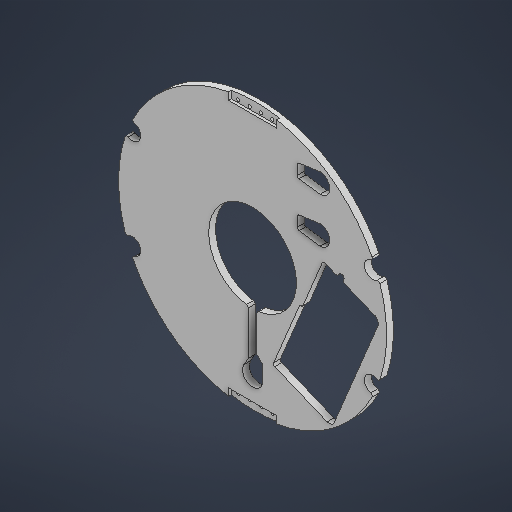
# Autodesk Inventor part: macro_mfd1004
Saved by Autodesk Inventor 2026.4 (Build 304435000, 435)
## iProperties
Created: 2026-11-03
Part Number: macro_mfd1004
Material: Genérico
Document SubType Name: Modeling
Designer: User
Density: 1 g/cm^3
Appearance: Padrão
Author: User
Autodesk Inventor part; units mm, degrees
ref_plane "YZ Plane" through (0, 0, 0) normal (1, 0, 0) x (0, 1, 0)
ref_plane "XZ Plane" through (0, 0, 0) normal (0, 1, 0) x (-1, 0, 0)
sketch "Sketch_Base_Disk" plane through (0, 0, 0) normal (0, 0, 1) x (1, 0, 0)
  circle A0 centre (0, 0) radius 195.5038
  dimension "d42" = 391.0076
  constraints: 1 centre point
  measures "d42" diameter of A0
extrude "Base_Disk" add sketch "Sketch_Base_Disk" along normal blind 10.0076
ref_plane "Datum_A_Front_Face" through (0, 0, 10.0076) normal (0, 0, 1) x (1, 0, 0)
sketch "Sketch_Central_Bore_Keyhole" plane through (0, 0, 0) normal (0, 0, 1) x (1, 0, 0)
  circle A0 centre (0.0002, 0.1535) radius 64.008
  line L0 (-6.2988, -51.2066) -> (6.4012, -51.2066)
  line L1 (6.4012, -51.2066) -> (6.4012, -130.0469)
  line L2 (6.4012, -130.0469) -> (-6.2988, -130.0469)
  line L3 (-6.2988, -130.0469) -> (-6.2988, -51.2066)
  circle A1 centre (0.051, -148.5127) radius 14.732
  line L4 (0.0002, 243.0256) -> (0.0002, -242.7185)
  line L5 (14.7822, -148.6669) -> (14.7822, -127.3309)
  line L6 (14.7822, -127.3309) -> (89.3002, -201.8489)
  line L7 (14.7822, -127.3309) -> (6.4012, -118.9484)
  line L8 (-6.2988, -130.0469) -> (-67.6388, -236.2908)
  line L9 (-6.2988, -130.0469) -> (-12.7075, -141.1471)
  point P0 (6.4012, -63.5336)
  point P1 (-6.2988, -63.5438)
  point P2 (-12.7073, -141.1467)
  point P3 (14.7822, -148.3584)
  dimension "d31" = 29.464
  dimension "d28" = 128.016
  dimension "d29" = 12.7
  dimension "d30" = 148.6662
  dimension "d33" = 21.336
  dimension "d34" = 45
  dimension "d35" = 18.4658
  dimension "d36" = 30
  constraints: 20 end point, 2 parallel, 2 point on line, 2 vertical, 1 centre point, 1 horizontal, 1 midpoint, 1 perpendicular, 4 other
  measures "d28" diameter of A0
  measures "d29" distance between parallel lines of L3 L1
  measures "d30" distance of point (0.051, -148.513) A0.centre
  measures "d33" distance of L5.start L5.end
  measures "d34" angle of L4 L6
  measures "d35" distance from line of L2 point (0.051, -148.513)
  measures "d36" angle of L4 L8
extrude "Central_Bore_Keyhole" cut sketch "Sketch_Central_Bore_Keyhole" along normal through all both and the other way through all
sketch "Sketch_Flats_Notches" plane through (0, 0, 0) normal (0, 0, 1) x (1, 0, 0)
  line L0 (0, 195.5038) -> (0, -195.5038)
  line L1 (195.5038, 0) -> (-195.5038, 0)
  line L2 (-270.4451, 112.022) -> (270.4451, -112.022)
  line L3 (297.3467, 123.165) -> (-297.3467, -123.165)
  circle A0 centre (0, 0) radius 195.5038 projected
  line L4 (180.622, -74.8161) -> (174.99, -72.4832)
  circle A1 centre (174.99, -72.4832) radius 12.0015
  circle A2 centre (0, 0) radius 189.4078
  circle A3 centre (-174.99, -72.4832) radius 12.0015
  circle A4 centre (-174.99, 72.4832) radius 12.0015
  circle A5 centre (174.99, 72.4832) radius 12.0015
  dimension "d21" = 67.5
  dimension "d22" = 67.5
  dimension "d23" = 6.096
  dimension "d24" = 24.003
  dimension "d25" = 24.003
  dimension "d26" = 24.003
  dimension "d27" = 24.003
  constraints: 10 end point, 5 centre point, 5 point on circle, 5 point on line, 4 midpoint, 2 coincident, 1 vertical
  measures "d21" angle of L0 L2
  measures "d22" angle of L0 L3
  measures "d23" distance of L4.start L4.end
  measures "d24" diameter of A1
  measures "d25" diameter of A3
  measures "d26" diameter of A4
  measures "d27" diameter of A5
extrude "Flats_Notches_DetailA" cut sketch "Sketch_Flats_Notches" along normal through all both and the other way through all contours A5 L3 A0 | A0 L3 A2 A5 | A4 A2 L2 A0 | A0 L2 A4 | A2 L3 A5 | A4 L2 A2 | A0 A5 A2 L3 | L3 A5 A0 | A0 A4 L2 | L2 A2 A4 A0 | A4 A2 L2 | A1 A2 L2 | L2 A2 A1 | L3 A2 A5 | A3 A2 L3 | L3 A2 A3 | A3 A0 L3 A2 | A2 L2 A0 A1 | A1 A0 L2 A2 | A2 L3 A0 A3 | A3 L3 A0 | A0 L2 A1 | A1 L2 A0 | A0 L3 A3
sketch "Sketch_Mount_Pockets" plane through (0, 0, 10.0076) normal (0, 0, 1) x (1, 0, 0)
  line L0 (-35.1155, 181.61) -> (35.1155, 181.61)
  line L1 (35.1155, 181.61) -> (35.1155, 215.9)
  line L2 (35.1155, 215.9) -> (-35.1155, 215.9)
  line L3 (-35.1155, 215.9) -> (-35.1155, 181.61)
  line L4 (-35.1155, -215.9) -> (35.1155, -215.9)
  line L5 (35.1155, -215.9) -> (35.1155, -181.61)
  line L6 (35.1155, -181.61) -> (-35.1155, -181.61)
  line L7 (-35.1155, -181.61) -> (-35.1155, -215.9)
  constraints: 16 end point, 4 parallel, 2 horizontal, 2 perpendicular
extrude "Front_Mount_Pockets" cut sketch "Sketch_Mount_Pockets" against normal blind 3.9624
sketch "Sketch_Back_Pockets" plane through (0, 0, 0) normal (0, 0, 1) x (1, 0, 0)
  line L0 (0, 0) -> (98.425, 0)
  line L1 (98.425, 0) -> (98.425, 287.782)
  arc A0 (6.4012, -63.5336) -> (-6.2988, -63.5438) centre (0.0002, 0.1535) ccw projected
  circle A1 centre (0.0002, 0.1535) radius 64.008
  line L2 (0.0002, 195.8109) -> (0.0002, -195.5038)
  arc A2 (-176.3434, -84.4082) -> (176.3434, -84.4082) centre (0, 0) ccw projected
  line L3 (-195.5038, 0) -> (195.5038, 0)
  arc A3 (98.425, 64.135) -> (98.425, 92.583) centre (98.425, 78.359) ccw
  line L4 (98.425, 78.359) -> (65.151, 78.359)
  line L5 (65.151, 85.2362) -> (65.151, 71.4818)
  line L6 (98.425, 92.583) -> (67.7728, 88.2542)
  line L7 (67.7728, 68.4637) -> (98.425, 64.135)
  arc A4 (67.7728, 88.2542) -> (65.151, 85.2362) centre (68.199, 85.2362) ccw
  arc A5 (65.151, 71.4818) -> (67.7728, 68.4637) centre (68.199, 71.4818) ccw
  arc A6 (98.425, 129.667) -> (98.425, 158.115) centre (98.425, 143.891) ccw
  line L8 (98.425, 143.891) -> (65.151, 143.891)
  line L9 (65.151, 150.7682) -> (65.151, 137.0138)
  line L10 (98.425, 158.115) -> (67.7728, 153.7862)
  line L11 (98.425, 129.667) -> (67.7728, 133.9957)
  arc A7 (67.7728, 153.7862) -> (65.151, 150.7682) centre (68.199, 150.7682) ccw
  arc A8 (65.151, 137.0138) -> (67.7728, 133.9957) centre (68.199, 137.0138) ccw
  line L12 (98.425, 129.667) -> (65.151, 129.667)
  line L13 (98.425, 92.583) -> (65.151, 92.583)
  point P0 (65.151, 68.834)
  point P1 (65.151, 87.884)
  point P2 (65.151, 134.366)
  point P3 (65.151, 153.416)
  dimension "d57" = 98.425
  dimension "d90" = 90
  dimension "d94" = 14.224
  dimension "d95" = 78.359
  dimension "d96" = 33.274
  dimension "d97" = 19.05
  dimension "d98" = 3.048
  dimension "d99" = 14.224
  dimension "d100" = 143.891
  dimension "d101" = 33.274
  dimension "d102" = 19.05
  dimension "d103" = 3.048
  dimension "d104" = 8.038
  dimension "d105" = 8.038
  constraints: 26 end point, 13 point on circle, 9 point on line, 8 tangent, 7 centre point, 5 horizontal, 4 midpoint, 3 vertical, 2 coincident, 2 equal radius, 10 other
  measures "d57" distance of L0.start L0.end
  measures "d90" angle to the sketch y axis of L0
  measures "d94" radius of A3
  measures "d95" distance of L4.start L0.end
  measures "d96" distance of L4.start L4.end
  measures "d97" distance of point (65.151, 87.884) point (65.151, 68.834)
  measures "d98" radius of A4
  measures "d99" radius of A6
  measures "d100" distance of L0.end L8.start
  measures "d101" distance of L8.start L8.end
  measures "d102" distance of point (65.151, 153.416) point (65.151, 134.366)
  measures "d103" radius of A7
  measures "d104" angle of L13 L6
  measures "d105" angle of L11 L12
extrude "Back_Pockets_and_Slots" cut sketch "Sketch_Back_Pockets" along normal through all contours L11 A8 L9 L8 L1 | L1 A6 | L7 A5 L5 L4 L1 | L1 A3 | L4 L5 A4 L6 L1 | L8 L9 A7 L10 L1
sketch "Sketch_Mount_Holes" plane through (0, 0, 10.0076) normal (0, 0, 1) x (1, 0, 0)
  circle A0 centre (-24.8158, 185.42) radius 2.4892
  circle A1 centre (-24.8158, -185.42) radius 2.4892
  circle A2 centre (-8.255, 185.42) radius 2.4892
  circle A3 centre (-8.255, -185.42) radius 2.4892
  circle A4 centre (8.255, 185.42) radius 2.4892
  circle A5 centre (8.255, -185.42) radius 2.4892
  circle A6 centre (24.8158, 185.42) radius 2.4892
  circle A7 centre (24.8158, -185.42) radius 2.4892
  constraints: 8 centre point
extrude "Mount_Pocket_Holes" cut sketch "Sketch_Mount_Holes" along normal through all both and the other way through all
sketch "Esboço11" plane through (0, 0, 0) normal (0, 0, -1) x (-1, 0, 0)
  arc A0 (-176.3434, -84.4082) -> (-184.3792, -65.008) centre (-174.99, -72.4832) ccw projected
  circle A1 centre (-174.99, -72.4832) radius 12.0015
  line L0 (174.99, 72.4832) -> (-174.99, -72.4832)
  line L1 (0, 0) -> (-67.6071, -28.0038)
  line L2 (-67.6071, -28.0038) -> (-30.7085, -117.085)
  line L3 (-32.358, -121.0674) -> (-108.7651, -152.7162)
  line L4 (-119.053, -148.4549) -> (-182.9727, 5.8611)
  line L5 (-67.6071, -28.0038) -> (-67.9941, -27.0694)
  line L6 (-70.8101, -25.1878) -> (-70.6684, -25.1878)
  line L7 (-73.4844, -23.3062) -> (-101.6776, 44.7583)
  arc A2 (-178.7113, 16.149) -> (-182.9727, 5.8611) centre (-175.6981, 8.8744) ccw
  arc A3 (-119.053, -148.4549) -> (-108.7651, -152.7162) centre (-111.7783, -145.4416) ccw
  arc A4 (-101.6776, 44.7583) -> (-105.66, 46.4078) centre (-104.4936, 43.5919) ccw
  arc A5 (-67.9941, -27.0694) -> (-70.8101, -25.1878) centre (-70.8101, -28.2358) ccw
  arc A6 (-73.4844, -23.3062) -> (-70.6684, -25.1878) centre (-70.6684, -22.1398) ccw
  arc A7 (-32.358, -121.0674) -> (-30.7085, -117.085) centre (-33.5244, -118.2514) ccw
  line L8 (-132.8273, 38.4539) -> (-133.4106, 39.8619)
  line L9 (-125.4354, 41.5157) -> (-126.0186, 42.9237)
  line L10 (-130.001, 44.5733) -> (-131.761, 43.8443)
  line L11 (-134.4769, 34.4715) -> (-178.7113, 16.149)
  line L12 (-121.453, 39.8662) -> (-105.66, 46.4078)
  arc A8 (-125.4354, 41.5157) -> (-121.453, 39.8662) centre (-122.6194, 42.6822) ccw
  arc A9 (-131.761, 43.8443) -> (-133.4106, 39.8619) centre (-130.5946, 41.0283) ccw
  arc A10 (-134.4769, 34.4715) -> (-132.8273, 38.4539) centre (-135.6433, 37.2875) ccw
  arc A11 (-126.0186, 42.9237) -> (-130.001, 44.5733) centre (-128.8346, 41.7573) ccw
  point P0 (-29.542, -119.901)
  point P1 (-116.0397, -155.7295)
  point P2 (-185.986, 13.1357)
  point P3 (-68.7735, -25.1878)
  point P4 (-124.269, 38.6998)
  point P5 (-131.6609, 35.6379)
  point P6 (-134.577, 42.6779)
  dimension "d37" = 73.1774
  dimension "d39" = 91.8972
  dimension "d40" = 93.6244
  dimension "d41" = 182.7784
  dimension "d43" = 3.048
  dimension "d45" = 7.874
  dimension "d46" = 3.048
  dimension "d47" = 3.048
  dimension "d48" = 3.048
  dimension "d50" = 8.001
  dimension "d51" = 7.62
  dimension "d52" = 3.048
  dimension "d53" = 3.048
  constraints: 26 end point, 20 point on circle, 20 tangent, 14 point on line, 11 centre point, 4 equal radius, 4 perpendicular, 1 coincident, 1 midpoint, 1 parallel
  measures "d37" distance of L1.start L1.end
  measures "d39" vertical distance of point (-29.542, -119.901) L1.end
  measures "d40" distance of point (-29.542, -119.901) point (-116.04, -155.729)
  measures "d41" distance of point (-116.04, -155.729) point (-185.986, 13.136)
  measures "d43" distance of L1.end point (-68.774, -25.188)
  measures "d45" radius of A2
  measures "d46" radius of A4
  measures "d47" radius of A6
  measures "d48" radius of A7
  measures "d50" distance of point (-124.269, 38.7) point (-131.661, 35.638)
  measures "d51" distance of point (-131.661, 35.638) point (-134.577, 42.678)
  measures "d52" radius of A8
  measures "d53" radius of A11
extrude "Extrusão11" cut sketch "Esboço11" against normal through all contours L4 A2 L11 A10 L8 A9 L10 A11 L9 A8 L12 A4 L7 A6 A5 L5 L0 | L0 L2 A7 L3 A3 L4
fillet "Arredondamento1" radius 3.048 10 edges at (6.4012, -63.5336, 5.0038) (-6.2988, -63.5438, 5.0038) (-176.3434, -84.4082, 5.0038) (-184.3792, -65.008, 5.0038) (-176.3434, 84.4082, 5.0038) (-184.3792, 65.008, 5.0038) (184.3792, -65.008, 5.0038) (176.3434, -84.4082, 5.0038) (184.3792, 65.008, 5.0038) (176.3434, 84.4082, 5.0038)
